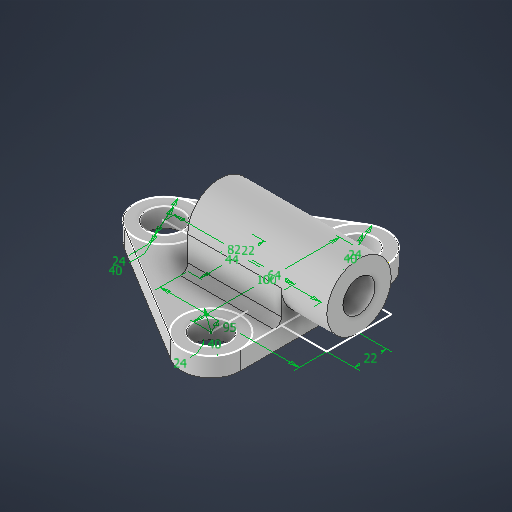
# Autodesk Inventor part: Peça4
Saved by Autodesk Inventor 2026.2 (Build 302298000, 298)
## iProperties
Created: 2026-08-07
Part Number: Peça4
Material: Genérico
Document SubType Name: Modeling
Designer: IFSP
Density: 1 g/cm^3
Appearance: Padrão
Author: IFSP
Autodesk Inventor part; units mm, degrees
ref_plane "YZ Plane" through (0, 0, 0) normal (1, 0, 0) x (0, 1, 0)
ref_plane "XZ Plane" through (0, 0, 0) normal (0, 1, 0) x (-1, 0, 0)
ref_plane "XY Plane" through (0, 0, 0) normal (0, 0, 1) x (1, 0, 0)
sketch "Esboço1" plane through (0, 0, 0) normal (0, 0, 1) x (1, 0, 0)
  circle A0 centre (0, 0) radius 12
  circle A1 centre (0, 0) radius 20
  line L0 (0, 0) -> (100, 0)
  circle A2 centre (100, 0) radius 20
  circle A3 centre (100, 0) radius 12
  line L1 (0, -20) -> (100, -20)
  line L2 (50, 0) -> (50, 82)
  circle A4 centre (50, 82) radius 20
  circle A5 centre (50, 82) radius 12
  line L3 (-17.0759, 10.4121) -> (32.9241, 92.4121)
  line L4 (67.0759, 92.4121) -> (117.0759, 10.4121)
  line L5 (50, -20) -> (50, 44)
  line L6 (50, 44) -> (28, 44)
  line L7 (28, 44) -> (72, 44)
  line L8 (72, 44) -> (72, -51)
  line L9 (72, -51) -> (50, -51)
  line L10 (50, -51) -> (28, -51)
  line L11 (28, -51) -> (28, 44)
  point P0 (72, -20)
  point P1 (28, -20)
  dimension "d0" = 24
  dimension "d1" = 40
  dimension "d2" = 100
  dimension "d3" = 40
  dimension "d4" = 24
  dimension "d5" = 82
  dimension "d6" = 40
  dimension "d7" = 24
  dimension "d8" = 64
  dimension "d15" = 22
  dimension "d16" = 44
  dimension "d17" = 95
  dimension "d18" = 22
  constraints: 24 end point, 6 centre point, 6 coincident, 6 point on circle, 6 tangent, 3 perpendicular, 3 point on line, 2 horizontal, 2 midpoint, 1 vertical
  measures "d0" diameter of A0
  measures "d1" diameter of A1
  measures "d2" distance of L0.start L0.end
  measures "d3" diameter of A2
  measures "d4" diameter of A3
  measures "d5" distance of L2.start L2.end
  measures "d6" diameter of A4
  measures "d7" diameter of A5
  measures "d8" distance of L5.start L5.end
  measures "d15" distance of L5.end L6.end
  measures "d16" distance of L6.end L7.end
  measures "d17" distance of L7.end L8.end
  measures "d18" distance of L8.end L9.end
extrude "Extrusão1" add sketch "Esboço1" along normal blind 13 contours A1 | A1 L3 A4 L2 L6 L11 L0 | L0 L11 L1 A1 | L11 L6 L2 L0 | L0 L5 L1 L11 | A4 | L2 L7 L8 L0 | L0 L8 L1 L5 | L4 A2 L0 L8 L7 L2 A4 | L0 A2 L1 L8 | A2
sketch "Esboço2" plane through (0, -20, 0) normal (0, -1, 0) x (1, 0, 0)
  point P0 (0, 0)
extrude "Extrusão2" add sketch "Esboço1" against normal blind 44 contours L11 L6 L2 L0 | L0 L5 L1 L11 | L2 L7 L8 L0 | L0 L8 L1 L5
extrude "Extrusão3" add sketch "Esboço1" against normal blind 44 contours L1 L8 L9 L10 L11
sketch "Esboço3" plane through (28, -51, 0) normal (0, -1, 0) x (1, 0, 0)
  line L0 (44, 0) -> (0, 0) projected
  arc A0 (0, -22) -> (44, -22) centre (22, -22) ccw
  line L1 (44, 0) -> (44, -22)
  line L2 (44, 0) -> (44, -44) projected
  line L3 (0, 0) -> (0, -22)
  line L4 (0, 0) -> (0, -44) projected
  line L5 (0, -44) -> (44, -44) projected
  line L6 (44, -44) -> (0, -44)
  line L7 (0, -44) -> (0, -22)
  point P0 (-28, 0)
  point P1 (22, -44)
  constraints: 8 end point, 4 midpoint, 2 point on circle, 1 centre point, 1 collinear, 1 perpendicular, 1 tangent
extrude "Extrusão4" cut sketch "Esboço3" against normal blind 95 contours L2 L5 A0 | A0 L5 L4
sketch "Esboço4" plane through (28, -51, 0) normal (0, -1, 0) x (1, 0, 0)
  line L0 (39.0759, 0) -> (4.9241, 0) projected
  line L1 (22, 0) -> (22, -22)
  circle A0 centre (22, -22) radius 22
  line L2 (44, 0) -> (44, -22) projected
  line L3 (44, 0) -> (44, -22)
  line L4 (4.9241, 0) -> (-45.0759, 0) projected
  line L5 (0, 0) -> (0, -22)
  line L6 (44, 0) -> (0, 0)
  point P0 (-28, 0)
  dimension "d27" = 22
  dimension "d28" = 44
  constraints: 8 end point, 2 collinear, 1 centre point, 1 coincident, 1 midpoint, 1 point on circle, 1 point on line, 1 tangent, 1 vertical
  measures "d27" distance of L1.start L1.end
  measures "d28" diameter of A0
extrude "Extrusão5" cut sketch "Esboço4" against normal blind 31 contours L6 L2 A0 L0 | A0 L5 L4 L0
sketch "Esboço5" plane through (50, -51, -22) normal (0, -1, 0) x (1, 0, 0)
  circle A0 centre (0, 0) radius 11
  point P0 (-50, 22)
  dimension "d31" = 22
  constraints: 1 centre point
  measures "d31" diameter of A0
extrude "Extrusão6" cut sketch "Esboço5" against normal blind 70
fillet "Arredondamento1" radius 5 2 edges at (72, 12, 0) (28, 12, 0)
